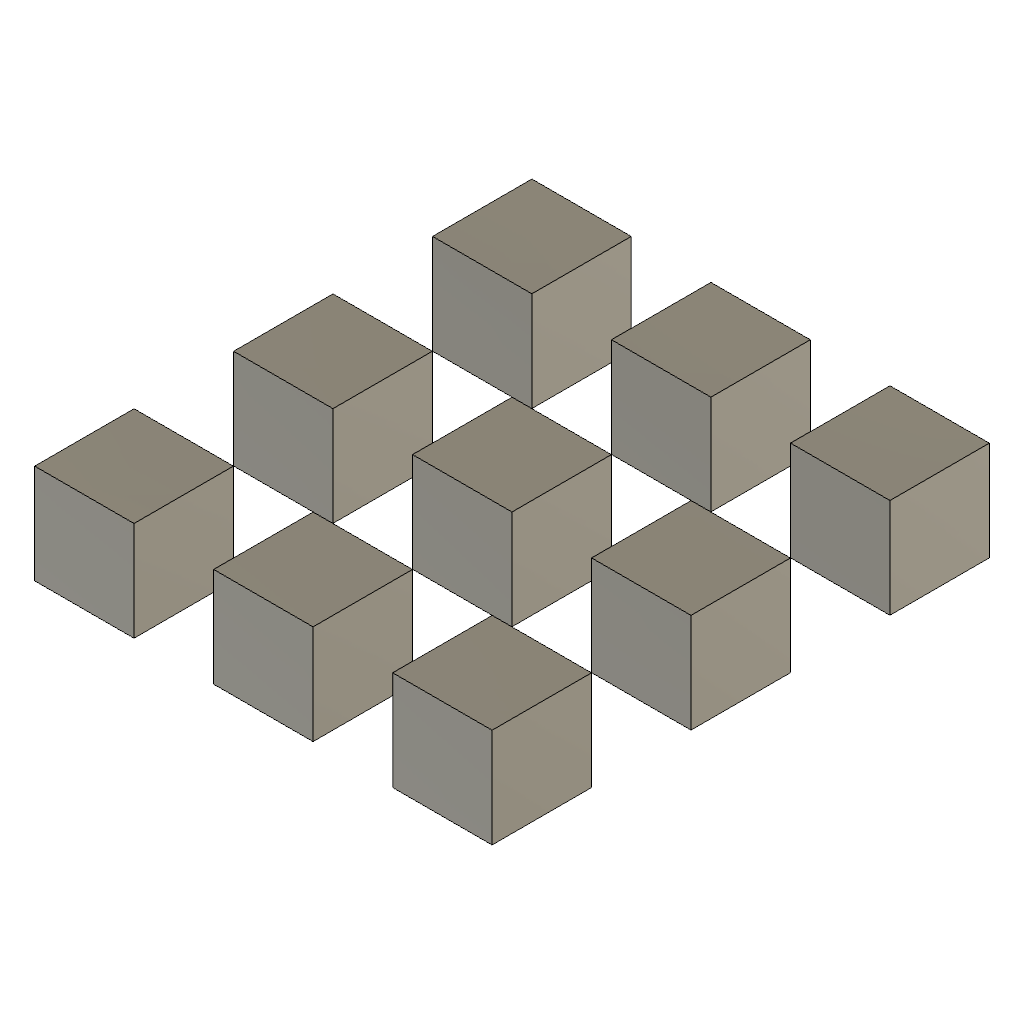
vendor_BodyRectPattern (Autodesk Fusion 360 design; units mm, degrees)
Autodesk Fusion 360 part; units mm, degrees
sketch "Cube sketch" plane through (0, 0, 0) normal (0, 0, 1) x (1, 0, 0)
  line L0 (0, 0) -> (10, 0)
  line L1 (10, 0) -> (10, 10)
  line L2 (10, 10) -> (0, 10)
  line L3 (0, 10) -> (0, 0)
extrude "Cube extrude" add sketch "Cube sketch" along normal blind 10 makes body 1
pattern_linear "Cube grid" count 3 spacing 18 along (1, 0, 0) count 3 spacing 20 along (0, 1, 0) of bodies 1 makes body 2 at (18, 6.6667, 3.3333) makes body 3 at (36, 6.6667, 3.3333) makes body 4 at (0, 26.6667, 3.3333) makes body 5 at (18, 26.6667, 3.3333) makes body 6 at (36, 26.6667, 3.3333) makes body 7 at (0, 46.6667, 3.3333) makes body 8 at (18, 46.6667, 3.3333) makes body 9 at (36, 46.6667, 3.3333)
equation "height = 20.0 mm"
